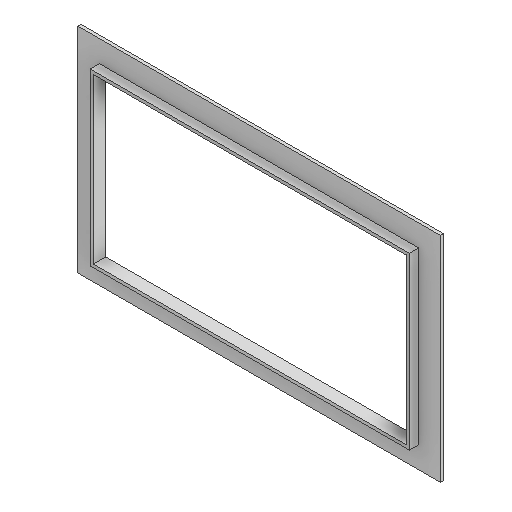
# Autodesk Inventor part: marco1
Saved by Autodesk Inventor 2025.2 (Build 292293000, 293)
## iProperties
Created: 2026-09-22
Part Number: marco1
Material: Genérico
Document SubType Name: Modeling
Designer: autor
Density: 1 g/cm^3
Appearance: Valor por defecto
Author: autor
Autodesk Inventor part; units mm, degrees
ref_plane "YZ Plane" through (0, 0, 0) normal (1, 0, 0) x (0, 1, 0)
ref_plane "XZ Plane" through (0, 0, 0) normal (0, 1, 0) x (-1, 0, 0)
ref_plane "XY Plane" through (0, 0, 0) normal (0, 0, 1) x (1, 0, 0)
sketch "Boceto1" plane through (0, 0, 0) normal (0, 0, 1) x (1, 0, 0)
  line L0 (-18.1001, 7.9394) -> (84.8999, 7.9394)
  line L1 (84.8999, 7.9394) -> (84.8999, -47.0606)
  line L2 (84.8999, -47.0606) -> (-18.1001, -47.0606)
  line L3 (-18.1001, -47.0606) -> (-18.1001, 7.9394)
  line L4 (91.8999, 14.9394) -> (-25.1001, 14.9394)
  line L5 (-25.1001, 14.9394) -> (-25.1001, -54.0606)
  line L6 (-25.1001, -54.0606) -> (91.8999, -54.0606)
  line L7 (91.8999, -54.0606) -> (91.8999, 14.9394)
  point P0 (0, 0)
  dimension "d0" = 103
  dimension "d1" = 55
  dimension "d2" = 7
  constraints: 16 end point, 4 parallel, 2 perpendicular, 1 horizontal, 3 other
  measures "d0" distance of L1.end L2.end
  measures "d1" distance of L0.end L1.end
  measures "d2" distance between parallel lines of L0 L4
extrude "Extrusión1" add sketch "Boceto1" along normal blind 1
sketch "Boceto2" plane through (0, 0, 1) normal (0, 0, 1) x (1, 0, 0)
  line L0 (-18.1001, 7.9394) -> (84.8999, 7.9394) projected
  line L1 (-18.1001, -47.0606) -> (-18.1001, 7.9394) projected
  line L2 (84.8999, -47.0606) -> (-18.1001, -47.0606) projected
  line L3 (84.8999, 7.9394) -> (84.8999, -47.0606) projected
  line L4 (-17.1001, 6.9394) -> (83.8999, 6.9394)
  line L5 (83.8999, 6.9394) -> (83.8999, -46.0606)
  line L6 (83.8999, -46.0606) -> (-17.1001, -46.0606)
  line L7 (-17.1001, -46.0606) -> (-17.1001, 6.9394)
  point P0 (0, 0)
  dimension "d5" = 1
  constraints: 8 end point, 3 other
  measures "d5" distance between parallel lines of L1 L7
extrude "Extrusión2" add sketch "Boceto2" along normal blind 3
sketch "Boceto3" plane through (0, 0, 1) normal (0, 0, -1) x (-1, 0, 0)
  line L0 (-84.8999, -47.0606) -> (18.1001, -47.0606) projected
  line L1 (18.1001, -47.0606) -> (18.1001, 7.9394) projected
  line L2 (18.1001, 7.9394) -> (-84.8999, 7.9394) projected
  line L3 (-84.8999, 7.9394) -> (-84.8999, -47.0606) projected
  line L4 (17.1001, 6.9394) -> (-83.8999, 6.9394) projected
  line L5 (17.1001, -46.0606) -> (17.1001, 6.9394) projected
  line L6 (-83.8999, -46.0606) -> (17.1001, -46.0606) projected
  line L7 (-83.8999, 6.9394) -> (-83.8999, -46.0606) projected
  point P0 (0, 0)
extrude "Extrusión3" add sketch "Boceto3" along normal up to surface (1 mm away)
